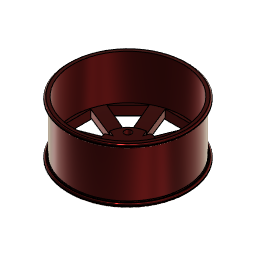
L1_Dobrescu_Diana (Autodesk Fusion 360 design; units mm, degrees)
Autodesk Fusion 360 part; units mm, degrees
sketch "Sketch1" plane through (0, 0, 0) normal (0, 1, 0) x (1, 0, 0)
  line L0 (0, 0) -> (0, -92.5)
  line L1 (0, -92.5) -> (200, -92.5)
  line L2 (200, -92.5) -> (200, -80)
  line L3 (200, -80) -> (190, -80)
  line L4 (190, 0) -> (0, 0)
  line L5 (190, -80) -> (190, 0)
  line L6 (0, 92.5) -> (200, 92.5)
  line L7 (0, 0) -> (0, 92.5)
  line L8 (200, 92.5) -> (200, 80)
  line L9 (200, 80) -> (190, 80)
  line L10 (190, 80) -> (190, 0)
  line L11 (190, 0) -> (0, 0)
  dimension "d1" = 200
  dimension "d2" = 92.5
  dimension "d3" = 12.5
  dimension "d4" = 10
  constraint coincident L0.start L4.end
  constraint vertical L0
  constraint perpendicular L0 L1
  constraint perpendicular L1 L2
  constraint perpendicular L2 L3
  constraint perpendicular L0 L4
  constraint perpendicular L3 L5
  constraint symmetric L0.start L4 L7.start
  constraint symmetric L0.end L4 L6.start
  constraint symmetric L1.end L4 L6.end
  constraint symmetric L2.end L4 L8.end
  constraint symmetric L3.end L4 L9.end
  constraint symmetric L5.end L4 L10.end
  measures "d1" distance of L0.end L1.end
  measures "d2" distance of L0.start L0.end
  measures "d3" distance of L1.end L2.end
  measures "d4" distance of L2.end L3.end
revolve "Revolve1" add sketch "Sketch1" angle 360 about axis through (0, 0, 0) along (0, 0, 1)
sketch "Sketch2" plane through (0, 0, 92.5) normal (0, 0, 1) x (-1, 0, 0)
  circle A0 centre (0, 0) radius 200
  circle A1 centre (-35.3553, 35.3553) radius 11.5
  circle A2 centre (35.3553, -35.3553) radius 11.5
  circle A3 centre (35.3553, 35.3553) radius 11.5
  circle A4 centre (-35.3553, -35.3553) radius 11.5
  point P0 (-35.3553, -35.3553)
  point P1 (35.3553, -35.3553)
  point P2 (35.3553, 35.3553)
  dimension "d6" = 23
  dimension "d8" = 360
  dimension "d9" = 23
  dimension "d10" = 23
  dimension "d11" = 23
  dimension "d12" = 100
  constraint coincident P1 A2.centre
  constraint coincident P2 A3.centre
  constraint coincident P0 A4.centre
  measures "d6" diameter of A1
  measures "d9" diameter of A2
  measures "d10" diameter of A3
  measures "d11" diameter of A4
  measures "d12" distance of A1.centre P1
extrude "Extrude1" cut sketch "Sketch2" against normal blind 340 contours A1 | A2 | A3 | A4
sketch "Sketch3" plane through (0, 0, 92.5) normal (0, 0, 1) x (-1, 0, 0)
  circle A0 centre (35.3553, -35.3553) radius 11.5
  circle A1 centre (-35.3553, -35.3553) radius 11.5
  circle A2 centre (35.3553, 35.3553) radius 11.5
  circle A3 centre (-35.3553, 35.3553) radius 11.5
  circle A4 centre (0, 0) radius 200
  line L0 (0, 175) -> (50, 175)
  line L1 (0, 175) -> (-50, 175)
  line L2 (0, 50) -> (50, 175)
  line L3 (0, 50) -> (-50, 175)
  line L4 (-123.7437, 123.7437) -> (-88.3883, 159.099)
  line L5 (-123.7437, 123.7437) -> (-159.099, 88.3883)
  line L6 (-43.6545, 54.7201) -> (-88.3883, 159.099)
  line L7 (-54.7201, 43.6545) -> (-159.099, 88.3883)
  line L8 (-175, 0) -> (-175, 50)
  line L9 (-175, 0) -> (-175, -50)
  line L10 (-50, 0) -> (-175, 50)
  line L11 (-50, 0) -> (-175, -50)
  line L12 (-123.7437, -123.7437) -> (-159.099, -88.3883)
  line L13 (-123.7437, -123.7437) -> (-88.3883, -159.099)
  line L14 (-54.7201, -43.6545) -> (-159.099, -88.3883)
  line L15 (-43.6545, -54.7201) -> (-88.3883, -159.099)
  line L16 (0, -175) -> (-50, -175)
  line L17 (0, -175) -> (50, -175)
  line L18 (0, -50) -> (-50, -175)
  line L19 (0, -50) -> (50, -175)
  line L20 (123.7437, -123.7437) -> (88.3883, -159.099)
  line L21 (123.7437, -123.7437) -> (159.099, -88.3883)
  line L22 (43.6545, -54.7201) -> (88.3883, -159.099)
  line L23 (54.7201, -43.6545) -> (159.099, -88.3883)
  line L24 (175, 0) -> (175, -50)
  line L25 (175, 0) -> (175, 50)
  line L26 (50, 0) -> (175, -50)
  line L27 (50, 0) -> (175, 50)
  line L28 (123.7437, 123.7437) -> (159.099, 88.3883)
  line L29 (123.7437, 123.7437) -> (88.3883, 159.099)
  line L30 (54.7201, 43.6545) -> (159.099, 88.3883)
  line L31 (43.6545, 54.7201) -> (88.3883, 159.099)
  circle A5 centre (0, 0) radius 70
  dimension "d15" = 50
  dimension "d16" = 125
  dimension "d21" = 140
  dimension "d22" = 175
  constraint coincident A4.centre A5.centre
  constraint coincident A5 L6.start
  constraint coincident A5 L7.start
  constraint coincident A5 L14.start
  constraint coincident A5 L15.start
  constraint coincident A5 L22.start
  constraint coincident A5 L23.start
  constraint coincident A5 L31.start
  constraint coincident A5 L30.start
  measures "d15" distance of A4.centre L2.start
  measures "d16" distance of L2.start L0.start
  measures "d21" diameter of A5
  measures "d22" distance of L0.start A4.centre
extrude "Extrude2" cut sketch "Sketch3" against normal blind 200 contours L0 L1 L2 L3 A5 | L2 L3 A5 | L28 L29 L30 L31 A5 | L4 L5 L6 L7 A5 | L26 L27 A5 | L24 L25 L26 L27 A5 | L8 L9 L10 L11 A5 | L10 L11 A5 | L12 L13 L14 L15 A5 | L20 L21 L22 L23 A5 | L16 L17 L18 L19 A5 | L18 L19 A5
sketch "Sketch4" plane through (0, 0, 92.5) normal (0, 0, 1) x (-1, 0, 0)
  line L0 (-88.3883, 159.099) -> (-43.6545, 54.7201)
  arc A0 (-43.6545, 54.7201) -> (-54.7201, 43.6545) centre (0, 0) ccw
  line L1 (-54.7201, 43.6545) -> (-159.099, 88.3883)
  line L2 (-159.099, 88.3883) -> (-88.3883, 159.099)
  line L3 (-50, 0) -> (-175, -50)
  line L4 (-175, -50) -> (-175, 50)
  line L5 (-175, 50) -> (-50, 0)
  line L6 (0, -50) -> (50, -175)
  line L7 (50, -175) -> (-50, -175)
  line L8 (-50, -175) -> (0, -50)
  line L9 (-159.099, -88.3883) -> (-54.7201, -43.6545)
  arc A1 (-54.7201, -43.6545) -> (-43.6545, -54.7201) centre (0, 0) ccw
  line L10 (-43.6545, -54.7201) -> (-88.3883, -159.099)
  line L11 (-88.3883, -159.099) -> (-159.099, -88.3883)
  line L12 (159.099, 88.3883) -> (54.7201, 43.6545)
  arc A2 (54.7201, 43.6545) -> (43.6545, 54.7201) centre (0, 0) ccw
  line L13 (43.6545, 54.7201) -> (88.3883, 159.099)
  line L14 (88.3883, 159.099) -> (159.099, 88.3883)
  line L15 (0, 50) -> (-50, 175)
  line L16 (-50, 175) -> (50, 175)
  line L17 (50, 175) -> (0, 50)
  line L18 (50, 0) -> (175, 50)
  line L19 (175, 50) -> (175, -50)
  line L20 (175, -50) -> (50, 0)
  line L21 (88.3883, -159.099) -> (43.6545, -54.7201)
  arc A3 (43.6545, -54.7201) -> (54.7201, -43.6545) centre (0, 0) ccw
  line L22 (54.7201, -43.6545) -> (159.099, -88.3883)
  line L23 (159.099, -88.3883) -> (88.3883, -159.099)
  circle A4 centre (35.3553, -35.3553) radius 11.5
  circle A5 centre (-35.3553, -35.3553) radius 11.5
  circle A6 centre (35.3553, 35.3553) radius 11.5
  circle A7 centre (-35.3553, 35.3553) radius 11.5
  circle A8 centre (0, 0) radius 200
  circle A9 centre (0, 0) radius 70
  circle A10 centre (0, 0) radius 185
  dimension "d25" = 140
  dimension "d26" = 370
  constraint concentric A0 A9
  constraint concentric A0 A10
  measures "d25" diameter of A9
  measures "d26" diameter of A10
extrude "Extrude3" cut sketch "Sketch4" against normal blind 150 contours A10
extrude "Extrude4" cut 1 faces at (-8.9751, -9.1778, 92.5) along direction (0, 0, -1) blind 140
fillet "Fillet1" radius 5 1 edges at (-186.4655, -72.3231, 92.5)
fillet "Fillet2" radius 5 1 edges at (-186.4655, -72.3231, -92.5)
chamfer "Chamfer1" distance 5 angle 45 4 edges at (46.0771, -31.1968, -92.5) (-24.6336, -31.1968, -92.5) (-24.6336, 39.5139, -92.5) (46.0771, 39.5139, -92.5)
fillet "Fillet5" radius 2 1 edges at (-177.1422, -68.7069, 80)
fillet "Fillet6" radius 2 1 edges at (-177.1422, -68.7069, -80)
fillet "Fillet7" radius 5 1 edges at (-186.4655, -72.3231, -80)
fillet "Fillet8" radius 5 1 edges at (-186.4655, -72.3231, 80)
chamfer "Chamfer2" distance 10 angle 45 16 edges at (66.0214, 106.9095, -92.5) (106.9095, 66.0214, -92.5) (112.5, 25, -92.5) (112.5, -25, -92.5) (106.9095, -66.0214, -92.5) (66.0214, -106.9095, -92.5) (25, -112.5, -92.5) (-25, -112.5, -92.5) (-66.0214, -106.9095, -92.5) (-106.9095, -66.0214, -92.5) (-112.5, -25, -92.5) (-112.5, 25, -92.5) (-106.9095, 66.0214, -92.5) (-66.0214, 106.9095, -92.5) (-25, 112.5, -92.5) (25, 112.5, -92.5)
chamfer "Chamfer3" distance 5 angle 45 8 edges at (123.7437, 123.7437, -92.5) (175, 0, -92.5) (123.7437, -123.7437, -92.5) (0, -175, -92.5) (-123.7437, -123.7437, -92.5) (-175, 0, -92.5) (-123.7437, 123.7437, -92.5) (0, 175, -92.5)
fillet "Fillet9" radius 5 4 edges at (-49.4975, 49.4975, -92.5) (49.4975, 49.4975, -92.5) (49.4975, -49.4975, -92.5) (-49.4975, -49.4975, -92.5)
